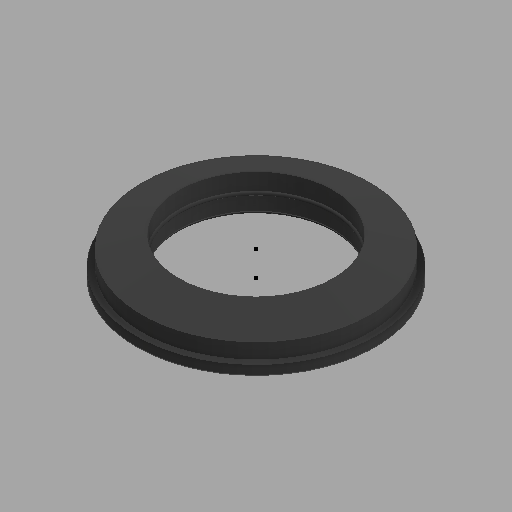
# Autodesk Inventor part: GEA670i208001 Seal, Can Lip
Saved by Autodesk Inventor 2027.1 (Build 311270010, 270A)
## iProperties
Created: 2026-11-09
Part Number: GEA670i208001 Seal, Can Lip
Material: Generic
Document SubType Name: Modeling
Designer: migue
Density: 1 g/cm^3
Appearance: Default
Author: migue
Autodesk Inventor part; units mm, degrees
ref_plane "YZ Plane" through (0, 0, 0) normal (1, 0, 0) x (0, 1, 0)
ref_plane "XZ Plane" through (0, 0, 0) normal (0, 1, 0) x (-1, 0, 0)
sketch "Sketch1" plane through (0, 0, 0) normal (0, 1, 0) x (-1, 0, 0)
  circle A0 centre (0, 0) radius 38
  circle A1 centre (0, 0) radius 24.5
  dimension "d0" = 76
  dimension "d1" = 49
  constraints: 2 centre point, 2 coincident
  measures "d0" diameter of A0
  measures "d1" diameter of A1
extrude "Extrusion1" add sketch "Sketch1" along normal blind 3
sketch "Sketch2" plane through (0, 3, 0) normal (0, 1, 0) x (1, 0, 0)
  circle A0 centre (0, 0) radius 36.25
  circle A1 centre (0, 0) radius 24.5 projected
  dimension "d4" = 72.5
  constraints: 1 centre point, 1 coincident
  measures "d4" diameter of A0
extrude "Extrusion2" add sketch "Sketch2" along normal blind 5
sketch "Sketch3" plane through (0, 8, 0) normal (0, 1, 0) x (1, 0, 0)
  point P0 (0, 0)
ref_plane "Work Plane1" through (0, 12, 0) normal (0, 1, 0) x (1, 0, 0)
sketch "Sketch4" plane through (0, 12, 0) normal (0, 1, 0) x (1, 0, 0)
  circle A0 centre (0, 0) radius 24.5 projected
loft "Loft1" add profiles "Sketch4" section 1 edges at (-36.25, 8, 0)
sketch "Sketch6" plane through (0, 0, 0) normal (1, 0, 0) x (0, 1, 0)
  point P0 (0, 0)
extrude "Extrusion4" cut sketch "Sketch1" along normal through all both and the other way through all contours A1
sketch "Sketch7" plane through (0, 0, 0) normal (0, -1, 0) x (1, 0, 0)
  point P0 (0, 0)
sketch "Sketch8" plane through (0, 0, 0) normal (1, 0, 0) x (0, 1, 0)
  line L0 (12, -24.5) -> (0, -24.5) projected
  arc A0 (6.5, -24.5) -> (5.5, -24.5) centre (6, -24.5) ccw
  line L1 (-2.4, 0) -> (14.4, 0) projected
  point P0 (0, 0)
  dimension "d16" = 1
  dimension "d18" = 6
  constraints: 2 point on circle, 2 point on line, 1 centre point, 1 midpoint
  measures "d16" diameter of A0
  measures "d18" distance of L0.start A0.centre
revolve "Revolution1" add sketch "Sketch8" angle 360 about axis through (0, -10, 0) along (0, 1, 0)
fillet "Fillet1" radius 1 1 edges at (24.5, 0, 0)
body "Solid1"
